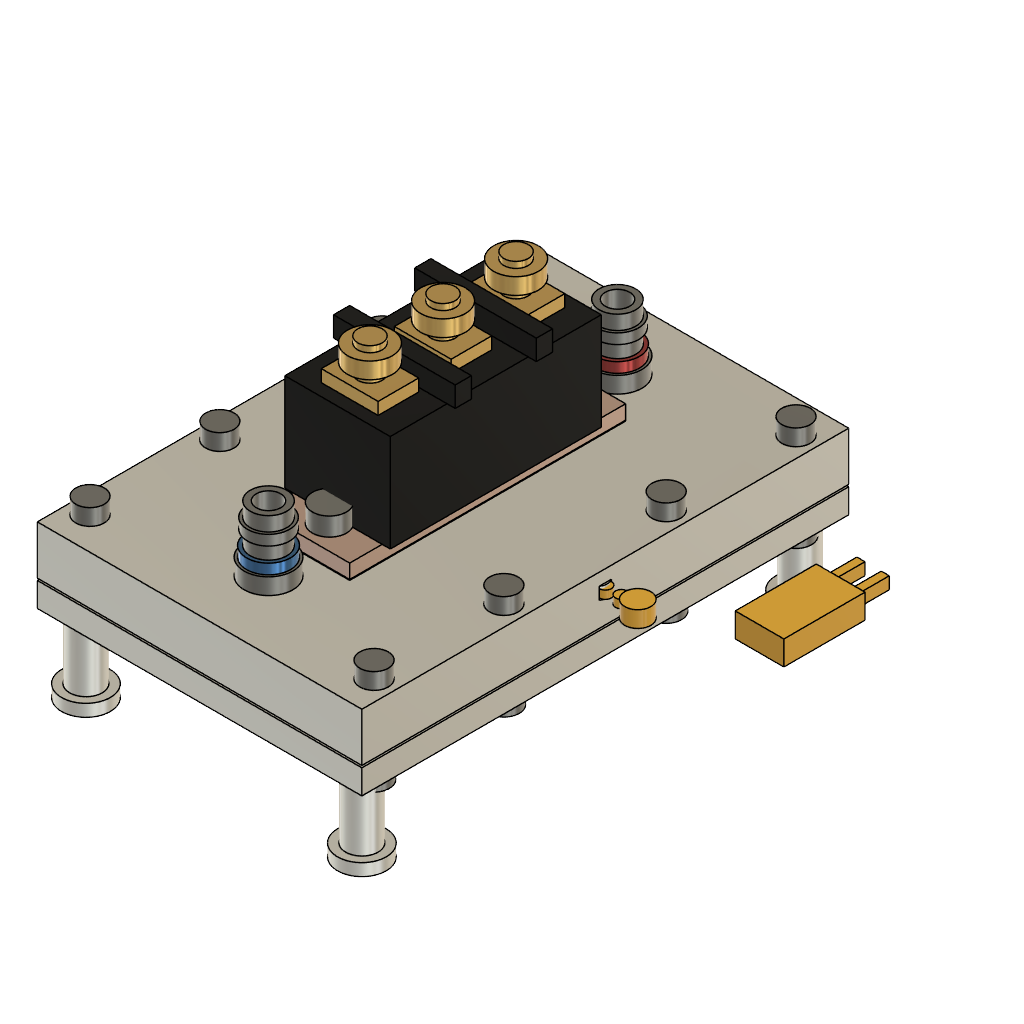
Before_Review_Backup (Autodesk Fusion 360 design; units mm, degrees)
part number: 2026-11-02-01-28-30-721
part number: 2026-11-02-02-59-40-221
part number: 2026-11-02-02-59-43-084
part number: 2026-11-02-02-59-43-519
part number: 2026-11-02-02-59-44-128
part number: 2026-11-02-02-59-44-602
part number: 2026-11-02-02-59-44-987
part number: 2026-11-02-02-59-46-241
part number: 2026-11-02-02-59-47-034
part number: 2026-11-02-02-59-47-858
part number: 2026-11-02-02-59-48-789
part number: 2026-11-02-02-59-49-745
part number: 2026-11-02-02-59-54-096
part number: 2026-11-02-02-59-54-882
part number: 2026-11-02-02-59-56-951
part number: 2026-11-02-03-00-06-820
part number: 2026-11-02-03-00-18-161
part number: 2026-11-02-03-00-22-757
Autodesk Fusion 360 part; units mm, degrees
(part 1 of 2)
ref_plane "WorkPlane1" through (0, 0, 0) normal (0, 0, 1) x (1, 0, 0) in component "01 Cold plate | 6061-T6 Aluminium | 120 x 80 x 12 mm"
sketch "Cold plate stock sketch" plane through (0, 0, 0) normal (0, 0, 1) x (1, 0, 0) in component "01 Cold plate | 6061-T6 Aluminium | 120 x 80 x 12 mm"
  line L0 (0, 0) -> (80, 0)
  line L1 (80, 0) -> (80, 120)
  line L2 (80, 120) -> (0, 120)
  line L3 (0, 120) -> (0, 0)
extrude "Cold plate stock" add sketch "Cold plate stock sketch" along normal blind 12 makes body 1 in component "01 Cold plate | 6061-T6 Aluminium | 120 x 80 x 12 mm"
ref_plane "WorkPlane2" through (0, 0, 0) normal (0, 0, 1) x (1, 0, 0) in component "01 Cold plate | 6061-T6 Aluminium | 120 x 80 x 12 mm"
sketch "16 Mini-Channels | 2 x 5 x 70 mm sketch" plane through (0, 0, 0) normal (0, 0, 1) x (1, 0, 0) in component "01 Cold plate | 6061-T6 Aluminium | 120 x 80 x 12 mm"
  line L0 (12.75, 25) -> (14.75, 25)
  line L1 (14.75, 25) -> (14.75, 95)
  line L2 (14.75, 95) -> (12.75, 95)
  line L3 (12.75, 95) -> (12.75, 25)
  line L4 (16.25, 25) -> (18.25, 25)
  line L5 (18.25, 25) -> (18.25, 95)
  line L6 (18.25, 95) -> (16.25, 95)
  line L7 (16.25, 95) -> (16.25, 25)
  line L8 (19.75, 25) -> (21.75, 25)
  line L9 (21.75, 25) -> (21.75, 95)
  line L10 (21.75, 95) -> (19.75, 95)
  line L11 (19.75, 95) -> (19.75, 25)
  line L12 (23.25, 25) -> (25.25, 25)
  line L13 (25.25, 25) -> (25.25, 95)
  line L14 (25.25, 95) -> (23.25, 95)
  line L15 (23.25, 95) -> (23.25, 25)
  line L16 (26.75, 25) -> (28.75, 25)
  line L17 (28.75, 25) -> (28.75, 95)
  line L18 (28.75, 95) -> (26.75, 95)
  line L19 (26.75, 95) -> (26.75, 25)
  line L20 (30.25, 25) -> (32.25, 25)
  line L21 (32.25, 25) -> (32.25, 95)
  line L22 (32.25, 95) -> (30.25, 95)
  line L23 (30.25, 95) -> (30.25, 25)
  line L24 (33.75, 25) -> (35.75, 25)
  line L25 (35.75, 25) -> (35.75, 95)
  line L26 (35.75, 95) -> (33.75, 95)
  line L27 (33.75, 95) -> (33.75, 25)
  line L28 (37.25, 25) -> (39.25, 25)
  line L29 (39.25, 25) -> (39.25, 95)
  line L30 (39.25, 95) -> (37.25, 95)
  line L31 (37.25, 95) -> (37.25, 25)
  line L32 (40.75, 25) -> (42.75, 25)
  line L33 (42.75, 25) -> (42.75, 95)
  line L34 (42.75, 95) -> (40.75, 95)
  line L35 (40.75, 95) -> (40.75, 25)
  line L36 (44.25, 25) -> (46.25, 25)
  line L37 (46.25, 25) -> (46.25, 95)
  line L38 (46.25, 95) -> (44.25, 95)
  line L39 (44.25, 95) -> (44.25, 25)
  line L40 (47.75, 25) -> (49.75, 25)
  line L41 (49.75, 25) -> (49.75, 95)
  line L42 (49.75, 95) -> (47.75, 95)
  line L43 (47.75, 95) -> (47.75, 25)
  line L44 (51.25, 25) -> (53.25, 25)
  line L45 (53.25, 25) -> (53.25, 95)
  line L46 (53.25, 95) -> (51.25, 95)
  line L47 (51.25, 95) -> (51.25, 25)
  line L48 (54.75, 25) -> (56.75, 25)
  line L49 (56.75, 25) -> (56.75, 95)
  line L50 (56.75, 95) -> (54.75, 95)
  line L51 (54.75, 95) -> (54.75, 25)
  line L52 (58.25, 25) -> (60.25, 25)
  line L53 (60.25, 25) -> (60.25, 95)
  line L54 (60.25, 95) -> (58.25, 95)
  line L55 (58.25, 95) -> (58.25, 25)
  line L56 (61.75, 25) -> (63.75, 25)
  line L57 (63.75, 25) -> (63.75, 95)
  line L58 (63.75, 95) -> (61.75, 95)
  line L59 (61.75, 95) -> (61.75, 25)
  line L60 (65.25, 25) -> (67.25, 25)
  line L61 (67.25, 25) -> (67.25, 95)
  line L62 (67.25, 95) -> (65.25, 95)
  line L63 (65.25, 95) -> (65.25, 25)
extrude "16 Mini-Channels | 2 x 5 x 70 mm" cut sketch "16 Mini-Channels | 2 x 5 x 70 mm sketch" along normal blind 5 bodies 1 in component "01 Cold plate | 6061-T6 Aluminium | 120 x 80 x 12 mm"
ref_plane "WorkPlane3" through (0, 0, 0) normal (0, 0, 1) x (1, 0, 0) in component "01 Cold plate | 6061-T6 Aluminium | 120 x 80 x 12 mm"
sketch "Headers sketch" plane through (0, 0, 0) normal (0, 0, 1) x (1, 0, 0) in component "01 Cold plate | 6061-T6 Aluminium | 120 x 80 x 12 mm"
  line L0 (10, 10) -> (70, 10)
  line L1 (70, 10) -> (70, 25)
  line L2 (70, 25) -> (10, 25)
  line L3 (10, 25) -> (10, 10)
  line L4 (10, 95) -> (70, 95)
  line L5 (70, 95) -> (70, 110)
  line L6 (70, 110) -> (10, 110)
  line L7 (10, 110) -> (10, 95)
extrude "Headers" cut sketch "Headers sketch" along normal blind 5 bodies 1 in component "01 Cold plate | 6061-T6 Aluminium | 120 x 80 x 12 mm"
ref_plane "WorkPlane4" through (0, 0, 0) normal (0, 0, 1) x (1, 0, 0) in component "01 Cold plate | 6061-T6 Aluminium | 120 x 80 x 12 mm"
sketch "Boundary-layer breaks sketch" plane through (0, 0, 0) normal (0, 0, 1) x (1, 0, 0) in component "01 Cold plate | 6061-T6 Aluminium | 120 x 80 x 12 mm"
  line L0 (14.7, 42) -> (16.3, 42)
  line L1 (16.3, 42) -> (16.3, 44.5)
  line L2 (16.3, 44.5) -> (14.7, 44.5)
  line L3 (14.7, 44.5) -> (14.7, 42)
  line L4 (14.7, 68) -> (16.3, 68)
  line L5 (16.3, 68) -> (16.3, 70.5)
  line L6 (16.3, 70.5) -> (14.7, 70.5)
  line L7 (14.7, 70.5) -> (14.7, 68)
  line L8 (18.2, 52) -> (19.8, 52)
  line L9 (19.8, 52) -> (19.8, 54.5)
  line L10 (19.8, 54.5) -> (18.2, 54.5)
  line L11 (18.2, 54.5) -> (18.2, 52)
  line L12 (18.2, 78) -> (19.8, 78)
  line L13 (19.8, 78) -> (19.8, 80.5)
  line L14 (19.8, 80.5) -> (18.2, 80.5)
  line L15 (18.2, 80.5) -> (18.2, 78)
  line L16 (21.7, 42) -> (23.3, 42)
  line L17 (23.3, 42) -> (23.3, 44.5)
  line L18 (23.3, 44.5) -> (21.7, 44.5)
  line L19 (21.7, 44.5) -> (21.7, 42)
  line L20 (21.7, 68) -> (23.3, 68)
  line L21 (23.3, 68) -> (23.3, 70.5)
  line L22 (23.3, 70.5) -> (21.7, 70.5)
  line L23 (21.7, 70.5) -> (21.7, 68)
  line L24 (25.2, 52) -> (26.8, 52)
  line L25 (26.8, 52) -> (26.8, 54.5)
  line L26 (26.8, 54.5) -> (25.2, 54.5)
  line L27 (25.2, 54.5) -> (25.2, 52)
  line L28 (25.2, 78) -> (26.8, 78)
  line L29 (26.8, 78) -> (26.8, 80.5)
  line L30 (26.8, 80.5) -> (25.2, 80.5)
  line L31 (25.2, 80.5) -> (25.2, 78)
  line L32 (28.7, 42) -> (30.3, 42)
  line L33 (30.3, 42) -> (30.3, 44.5)
  line L34 (30.3, 44.5) -> (28.7, 44.5)
  line L35 (28.7, 44.5) -> (28.7, 42)
  line L36 (28.7, 68) -> (30.3, 68)
  line L37 (30.3, 68) -> (30.3, 70.5)
  line L38 (30.3, 70.5) -> (28.7, 70.5)
  line L39 (28.7, 70.5) -> (28.7, 68)
  line L40 (32.2, 52) -> (33.8, 52)
  line L41 (33.8, 52) -> (33.8, 54.5)
  line L42 (33.8, 54.5) -> (32.2, 54.5)
  line L43 (32.2, 54.5) -> (32.2, 52)
  line L44 (32.2, 78) -> (33.8, 78)
  line L45 (33.8, 78) -> (33.8, 80.5)
  line L46 (33.8, 80.5) -> (32.2, 80.5)
  line L47 (32.2, 80.5) -> (32.2, 78)
  line L48 (35.7, 42) -> (37.3, 42)
  line L49 (37.3, 42) -> (37.3, 44.5)
  line L50 (37.3, 44.5) -> (35.7, 44.5)
  line L51 (35.7, 44.5) -> (35.7, 42)
  line L52 (35.7, 68) -> (37.3, 68)
  line L53 (37.3, 68) -> (37.3, 70.5)
  line L54 (37.3, 70.5) -> (35.7, 70.5)
  line L55 (35.7, 70.5) -> (35.7, 68)
  line L56 (39.2, 52) -> (40.8, 52)
  line L57 (40.8, 52) -> (40.8, 54.5)
  line L58 (40.8, 54.5) -> (39.2, 54.5)
  line L59 (39.2, 54.5) -> (39.2, 52)
  line L60 (39.2, 78) -> (40.8, 78)
  line L61 (40.8, 78) -> (40.8, 80.5)
  line L62 (40.8, 80.5) -> (39.2, 80.5)
  line L63 (39.2, 80.5) -> (39.2, 78)
  line L64 (42.7, 42) -> (44.3, 42)
  line L65 (44.3, 42) -> (44.3, 44.5)
  line L66 (44.3, 44.5) -> (42.7, 44.5)
  line L67 (42.7, 44.5) -> (42.7, 42)
  line L68 (42.7, 68) -> (44.3, 68)
  line L69 (44.3, 68) -> (44.3, 70.5)
  line L70 (44.3, 70.5) -> (42.7, 70.5)
  line L71 (42.7, 70.5) -> (42.7, 68)
  line L72 (46.2, 52) -> (47.8, 52)
  line L73 (47.8, 52) -> (47.8, 54.5)
  line L74 (47.8, 54.5) -> (46.2, 54.5)
  line L75 (46.2, 54.5) -> (46.2, 52)
  line L76 (46.2, 78) -> (47.8, 78)
  line L77 (47.8, 78) -> (47.8, 80.5)
  line L78 (47.8, 80.5) -> (46.2, 80.5)
  line L79 (46.2, 80.5) -> (46.2, 78)
  line L80 (49.7, 42) -> (51.3, 42)
  line L81 (51.3, 42) -> (51.3, 44.5)
  line L82 (51.3, 44.5) -> (49.7, 44.5)
  line L83 (49.7, 44.5) -> (49.7, 42)
  line L84 (49.7, 68) -> (51.3, 68)
  line L85 (51.3, 68) -> (51.3, 70.5)
  line L86 (51.3, 70.5) -> (49.7, 70.5)
  line L87 (49.7, 70.5) -> (49.7, 68)
  line L88 (53.2, 52) -> (54.8, 52)
  line L89 (54.8, 52) -> (54.8, 54.5)
  line L90 (54.8, 54.5) -> (53.2, 54.5)
  line L91 (53.2, 54.5) -> (53.2, 52)
  line L92 (53.2, 78) -> (54.8, 78)
  line L93 (54.8, 78) -> (54.8, 80.5)
  line L94 (54.8, 80.5) -> (53.2, 80.5)
  line L95 (53.2, 80.5) -> (53.2, 78)
  line L96 (56.7, 42) -> (58.3, 42)
  line L97 (58.3, 42) -> (58.3, 44.5)
  line L98 (58.3, 44.5) -> (56.7, 44.5)
  line L99 (56.7, 44.5) -> (56.7, 42)
  line L100 (56.7, 68) -> (58.3, 68)
  line L101 (58.3, 68) -> (58.3, 70.5)
  line L102 (58.3, 70.5) -> (56.7, 70.5)
  line L103 (56.7, 70.5) -> (56.7, 68)
  line L104 (60.2, 52) -> (61.8, 52)
  line L105 (61.8, 52) -> (61.8, 54.5)
  line L106 (61.8, 54.5) -> (60.2, 54.5)
  line L107 (60.2, 54.5) -> (60.2, 52)
  line L108 (60.2, 78) -> (61.8, 78)
  line L109 (61.8, 78) -> (61.8, 80.5)
  line L110 (61.8, 80.5) -> (60.2, 80.5)
  line L111 (60.2, 80.5) -> (60.2, 78)
  line L112 (63.7, 42) -> (65.3, 42)
  line L113 (65.3, 42) -> (65.3, 44.5)
  line L114 (65.3, 44.5) -> (63.7, 44.5)
  line L115 (63.7, 44.5) -> (63.7, 42)
  line L116 (63.7, 68) -> (65.3, 68)
  line L117 (65.3, 68) -> (65.3, 70.5)
  line L118 (65.3, 70.5) -> (63.7, 70.5)
  line L119 (63.7, 70.5) -> (63.7, 68)
extrude "Boundary-layer breaks" cut sketch "Boundary-layer breaks sketch" along normal blind 5 bodies 1 in component "01 Cold plate | 6061-T6 Aluminium | 120 x 80 x 12 mm"
ref_plane "WorkPlane5" through (0, 0, 0) normal (0, 0, 1) x (1, 0, 0) in component "01 Cold plate | 6061-T6 Aluminium | 120 x 80 x 12 mm"
sketch "Gasket groove 1 sketch" plane through (0, 0, 0) normal (0, 0, 1) x (1, 0, 0) in component "01 Cold plate | 6061-T6 Aluminium | 120 x 80 x 12 mm"
  line L0 (7, 7) -> (73, 7)
  line L1 (73, 7) -> (73, 9)
  line L2 (73, 9) -> (7, 9)
  line L3 (7, 9) -> (7, 7)
extrude "Gasket groove 1" cut sketch "Gasket groove 1 sketch" along normal blind 0.5 bodies 1 in component "01 Cold plate | 6061-T6 Aluminium | 120 x 80 x 12 mm"
ref_plane "WorkPlane6" through (0, 0, 0) normal (0, 0, 1) x (1, 0, 0) in component "01 Cold plate | 6061-T6 Aluminium | 120 x 80 x 12 mm"
sketch "Gasket groove 2 sketch" plane through (0, 0, 0) normal (0, 0, 1) x (1, 0, 0) in component "01 Cold plate | 6061-T6 Aluminium | 120 x 80 x 12 mm"
  line L0 (7, 111) -> (73, 111)
  line L1 (73, 111) -> (73, 113)
  line L2 (73, 113) -> (7, 113)
  line L3 (7, 113) -> (7, 111)
extrude "Gasket groove 2" cut sketch "Gasket groove 2 sketch" along normal blind 0.5 bodies 1 in component "01 Cold plate | 6061-T6 Aluminium | 120 x 80 x 12 mm"
ref_plane "WorkPlane7" through (0, 0, 0) normal (0, 0, 1) x (1, 0, 0) in component "01 Cold plate | 6061-T6 Aluminium | 120 x 80 x 12 mm"
sketch "Gasket groove 3 sketch" plane through (0, 0, 0) normal (0, 0, 1) x (1, 0, 0) in component "01 Cold plate | 6061-T6 Aluminium | 120 x 80 x 12 mm"
  line L0 (7, 9) -> (9, 9)
  line L1 (9, 9) -> (9, 111)
  line L2 (9, 111) -> (7, 111)
  line L3 (7, 111) -> (7, 9)
extrude "Gasket groove 3" cut sketch "Gasket groove 3 sketch" along normal blind 0.5 bodies 1 in component "01 Cold plate | 6061-T6 Aluminium | 120 x 80 x 12 mm"
ref_plane "WorkPlane8" through (0, 0, 0) normal (0, 0, 1) x (1, 0, 0) in component "01 Cold plate | 6061-T6 Aluminium | 120 x 80 x 12 mm"
sketch "Gasket groove 4 sketch" plane through (0, 0, 0) normal (0, 0, 1) x (1, 0, 0) in component "01 Cold plate | 6061-T6 Aluminium | 120 x 80 x 12 mm"
  line L0 (71, 9) -> (73, 9)
  line L1 (73, 9) -> (73, 111)
  line L2 (73, 111) -> (71, 111)
  line L3 (71, 111) -> (71, 9)
extrude "Gasket groove 4" cut sketch "Gasket groove 4 sketch" along normal blind 0.5 bodies 1 in component "01 Cold plate | 6061-T6 Aluminium | 120 x 80 x 12 mm"
ref_plane "WorkPlane9" through (0, 0, 12) normal (0, 0, 1) x (1, 0, 0) in component "01 Cold plate | 6061-T6 Aluminium | 120 x 80 x 12 mm"
sketch "Fluid port through-bores sketch" plane through (0, 0, 12) normal (0, 0, 1) x (1, 0, 0) in component "01 Cold plate | 6061-T6 Aluminium | 120 x 80 x 12 mm"
  circle A0 centre (40, 17) radius 3
  circle A1 centre (40, 103) radius 3
extrude "Fluid port through-bores" cut sketch "Fluid port through-bores sketch" against normal blind 7 bodies 1 in component "01 Cold plate | 6061-T6 Aluminium | 120 x 80 x 12 mm"
ref_plane "WorkPlane10" through (0, 0, 12) normal (0, 0, 1) x (1, 0, 0) in component "01 Cold plate | 6061-T6 Aluminium | 120 x 80 x 12 mm"
sketch "Cover bolt holes sketch" plane through (0, 0, 12) normal (0, 0, 1) x (1, 0, 0) in component "01 Cold plate | 6061-T6 Aluminium | 120 x 80 x 12 mm"
  circle A0 centre (5, 8) radius 2.2
  circle A1 centre (75, 8) radius 2.2
  circle A2 centre (5, 40) radius 2.2
  circle A3 centre (75, 40) radius 2.2
  circle A4 centre (5, 80) radius 2.2
  circle A5 centre (75, 80) radius 2.2
  circle A6 centre (5, 112) radius 2.2
  circle A7 centre (75, 112) radius 2.2
extrude "Cover bolt holes" cut sketch "Cover bolt holes sketch" against normal blind 12 bodies 1 in component "01 Cold plate | 6061-T6 Aluminium | 120 x 80 x 12 mm"
ref_plane "WorkPlane11" through (0, 0, 12) normal (0, 0, 1) x (1, 0, 0) in component "01 Cold plate | 6061-T6 Aluminium | 120 x 80 x 12 mm"
sketch "SCR M5 tapped holes sketch" plane through (0, 0, 12) normal (0, 0, 1) x (1, 0, 0) in component "01 Cold plate | 6061-T6 Aluminium | 120 x 80 x 12 mm"
  circle A0 centre (40, 32) radius 2.1
  circle A1 centre (40, 88) radius 2.1
extrude "SCR M5 tapped holes" cut sketch "SCR M5 tapped holes sketch" against normal blind 8 bodies 1 in component "01 Cold plate | 6061-T6 Aluminium | 120 x 80 x 12 mm"
ref_plane "WorkPlane12" through (0, 0, 6) normal (0, 0, 1) x (1, 0, 0) in component "01 Cold plate | 6061-T6 Aluminium | 120 x 80 x 12 mm"
sketch "Thermowell entry boss sketch" plane through (0, 0, 6) normal (0, 0, 1) x (1, 0, 0) in component "01 Cold plate | 6061-T6 Aluminium | 120 x 80 x 12 mm"
  circle A0 centre (78, 60) radius 2.5
extrude "Thermowell entry boss" add sketch "Thermowell entry boss sketch" along normal blind 3 bodies 1 in component "01 Cold plate | 6061-T6 Aluminium | 120 x 80 x 12 mm"
ref_plane "WorkPlane1" through (0, 0, 0) normal (0, 0, 1) x (1, 0, 0) in component "02 Perimeter sealing gasket | 0.5 mm silicone"
sketch "Gasket blank sketch" plane through (0, 0, 0) normal (0, 0, 1) x (1, 0, 0) in component "02 Perimeter sealing gasket | 0.5 mm silicone"
  line L0 (7, 7) -> (73, 7)
  line L1 (73, 7) -> (73, 113)
  line L2 (73, 113) -> (7, 113)
  line L3 (7, 113) -> (7, 7)
extrude "Gasket blank" add sketch "Gasket blank sketch" against normal blind 0.5 separate body makes body 2 in component "02 Perimeter sealing gasket | 0.5 mm silicone"
ref_plane "WorkPlane2" through (0, 0, 0) normal (0, 0, 1) x (1, 0, 0) in component "02 Perimeter sealing gasket | 0.5 mm silicone"
sketch "Gasket fluid aperture sketch" plane through (0, 0, 0) normal (0, 0, 1) x (1, 0, 0) in component "02 Perimeter sealing gasket | 0.5 mm silicone"
  line L0 (9, 9) -> (71, 9)
  line L1 (71, 9) -> (71, 111)
  line L2 (71, 111) -> (9, 111)
  line L3 (9, 111) -> (9, 9)
extrude "Gasket fluid aperture" cut sketch "Gasket fluid aperture sketch" against normal blind 0.5 bodies 2 in component "02 Perimeter sealing gasket | 0.5 mm silicone"
ref_plane "WorkPlane1" through (0, 0, -0.5) normal (0, 0, 1) x (1, 0, 0) in component "03 Bottom manifold cover | 6061-T6 Aluminium"
sketch "Bottom cover slab sketch" plane through (0, 0, -0.5) normal (0, 0, 1) x (1, 0, 0) in component "03 Bottom manifold cover | 6061-T6 Aluminium"
  line L0 (0, 0) -> (80, 0)
  line L1 (80, 0) -> (80, 120)
  line L2 (80, 120) -> (0, 120)
  line L3 (0, 120) -> (0, 0)
extrude "Bottom cover slab" add sketch "Bottom cover slab sketch" against normal blind 6 separate body makes body 3 in component "03 Bottom manifold cover | 6061-T6 Aluminium"
ref_plane "WorkPlane2" through (0, 0, -0.5) normal (0, 0, 1) x (1, 0, 0) in component "03 Bottom manifold cover | 6061-T6 Aluminium"
sketch "Cover bolt holes sketch (2)" plane through (0, 0, -0.5) normal (0, 0, 1) x (1, 0, 0) in component "03 Bottom manifold cover | 6061-T6 Aluminium"
  circle A0 centre (5, 8) radius 2.2
  circle A1 centre (75, 8) radius 2.2
  circle A2 centre (5, 40) radius 2.2
  circle A3 centre (75, 40) radius 2.2
  circle A4 centre (5, 80) radius 2.2
  circle A5 centre (75, 80) radius 2.2
  circle A6 centre (5, 112) radius 2.2
  circle A7 centre (75, 112) radius 2.2
extrude "Cover bolt holes'" cut sketch "Cover bolt holes sketch (2)" against normal blind 6 bodies 3 in component "03 Bottom manifold cover | 6061-T6 Aluminium"
ref_plane "WorkPlane1" through (0, 0, 12) normal (0, 0, 1) x (1, 0, 0) in component "04 Inlet hose barb fitting | 6 mm bore"
sketch "Hex collar sketch" plane through (0, 0, 12) normal (0, 0, 1) x (1, 0, 0) in component "04 Inlet hose barb fitting | 6 mm bore"
  circle A0 centre (40, 17) radius 6
extrude "Hex collar" add sketch "Hex collar sketch" along normal blind 4 separate body makes body 4 in component "04 Inlet hose barb fitting | 6 mm bore"
ref_plane "WorkPlane2" through (0, 0, 16) normal (0, 0, 1) x (1, 0, 0) in component "04 Inlet hose barb fitting | 6 mm bore"
sketch "Barb stem sketch" plane through (0, 0, 16) normal (0, 0, 1) x (1, 0, 0) in component "04 Inlet hose barb fitting | 6 mm bore"
  circle A0 centre (40, 17) radius 4.5
extrude "Barb stem" add sketch "Barb stem sketch" along normal blind 12 bodies 4 in component "04 Inlet hose barb fitting | 6 mm bore"
ref_plane "WorkPlane3" through (0, 0, 22) normal (0, 0, 1) x (1, 0, 0) in component "04 Inlet hose barb fitting | 6 mm bore"
sketch "Retention barb bead sketch" plane through (0, 0, 22) normal (0, 0, 1) x (1, 0, 0) in component "04 Inlet hose barb fitting | 6 mm bore"
  circle A0 centre (40, 17) radius 5.2
extrude "Retention barb bead" add sketch "Retention barb bead sketch" along normal blind 2.5 bodies 4 in component "04 Inlet hose barb fitting | 6 mm bore"
ref_plane "WorkPlane4" through (0, 0, 28) normal (0, 0, 1) x (1, 0, 0) in component "04 Inlet hose barb fitting | 6 mm bore"
sketch "Continuous fluid bore sketch" plane through (0, 0, 28) normal (0, 0, 1) x (1, 0, 0) in component "04 Inlet hose barb fitting | 6 mm bore"
  circle A0 centre (40, 17) radius 3
extrude "Continuous fluid bore" cut sketch "Continuous fluid bore sketch" against normal blind 16 bodies 4 in component "04 Inlet hose barb fitting | 6 mm bore"
ref_plane "WorkPlane1" through (0, 0, 16) normal (0, 0, 1) x (1, 0, 0) in component "05 Inlet anodized identification ring"
sketch "Identifier ring sketch" plane through (0, 0, 16) normal (0, 0, 1) x (1, 0, 0) in component "05 Inlet anodized identification ring"
  circle A0 centre (40, 17) radius 5.4
extrude "Identifier ring" add sketch "Identifier ring sketch" along normal blind 2.5 separate body makes body 5 in component "05 Inlet anodized identification ring"
ref_plane "WorkPlane2" through (0, 0, 16) normal (0, 0, 1) x (1, 0, 0) in component "05 Inlet anodized identification ring"
sketch "Ring bore sketch" plane through (0, 0, 16) normal (0, 0, 1) x (1, 0, 0) in component "05 Inlet anodized identification ring"
  circle A0 centre (40, 17) radius 4.5
extrude "Ring bore" cut sketch "Ring bore sketch" along normal blind 2.5 bodies 4 makes body 6 at (45.9702, 16.4026, 13.3333) in component "04 Inlet hose barb fitting | 6 mm bore"
extrude "Extrude2" cut sketch "Ring bore sketch" along normal blind 2.5 bodies 5 in component "05 Inlet anodized identification ring"
ref_plane "WorkPlane1" through (0, 0, 12) normal (0, 0, 1) x (1, 0, 0) in component "04 Outlet hose barb fitting | 6 mm bore"
sketch "Hex collar sketch (2)" plane through (0, 0, 12) normal (0, 0, 1) x (1, 0, 0) in component "04 Outlet hose barb fitting | 6 mm bore"
  circle A0 centre (40, 103) radius 6
extrude "Hex collar'" add sketch "Hex collar sketch (2)" along normal blind 4 separate body makes body 7 in component "04 Outlet hose barb fitting | 6 mm bore"
ref_plane "WorkPlane2" through (0, 0, 16) normal (0, 0, 1) x (1, 0, 0) in component "04 Outlet hose barb fitting | 6 mm bore"
sketch "Barb stem sketch (2)" plane through (0, 0, 16) normal (0, 0, 1) x (1, 0, 0) in component "04 Outlet hose barb fitting | 6 mm bore"
  circle A0 centre (40, 103) radius 4.5
extrude "Barb stem'" add sketch "Barb stem sketch (2)" along normal blind 12 bodies 7 in component "04 Outlet hose barb fitting | 6 mm bore"
ref_plane "WorkPlane3" through (0, 0, 22) normal (0, 0, 1) x (1, 0, 0) in component "04 Outlet hose barb fitting | 6 mm bore"
sketch "Retention barb bead sketch (2)" plane through (0, 0, 22) normal (0, 0, 1) x (1, 0, 0) in component "04 Outlet hose barb fitting | 6 mm bore"
  circle A0 centre (40, 103) radius 5.2
extrude "Retention barb bead'" add sketch "Retention barb bead sketch (2)" along normal blind 2.5 bodies 7 in component "04 Outlet hose barb fitting | 6 mm bore"
ref_plane "WorkPlane4" through (0, 0, 28) normal (0, 0, 1) x (1, 0, 0) in component "04 Outlet hose barb fitting | 6 mm bore"
sketch "Continuous fluid bore sketch (2)" plane through (0, 0, 28) normal (0, 0, 1) x (1, 0, 0) in component "04 Outlet hose barb fitting | 6 mm bore"
  circle A0 centre (40, 103) radius 3
extrude "Continuous fluid bore'" cut sketch "Continuous fluid bore sketch (2)" against normal blind 16 bodies 7 in component "04 Outlet hose barb fitting | 6 mm bore"
ref_plane "WorkPlane1" through (0, 0, 16) normal (0, 0, 1) x (1, 0, 0) in component "05 Outlet anodized identification ring"
sketch "Identifier ring sketch (2)" plane through (0, 0, 16) normal (0, 0, 1) x (1, 0, 0) in component "05 Outlet anodized identification ring"
  circle A0 centre (40, 103) radius 5.4
extrude "Identifier ring'" add sketch "Identifier ring sketch (2)" along normal blind 2.5 separate body makes body 8 in component "05 Outlet anodized identification ring"
ref_plane "WorkPlane2" through (0, 0, 16) normal (0, 0, 1) x (1, 0, 0) in component "05 Outlet anodized identification ring"
sketch "Ring bore sketch (2)" plane through (0, 0, 16) normal (0, 0, 1) x (1, 0, 0) in component "05 Outlet anodized identification ring"
  circle A0 centre (40, 103) radius 4.5
extrude "Ring bore'" cut sketch "Ring bore sketch (2)" along normal blind 2.5 bodies 7 makes body 9 at (45.9702, 102.4026, 13.3333) in component "04 Outlet hose barb fitting | 6 mm bore"
extrude "Extrude2'" cut sketch "Ring bore sketch (2)" along normal blind 2.5 bodies 8 in component "05 Outlet anodized identification ring"
ref_plane "WorkPlane1" through (0, 0, 12) normal (0, 0, 1) x (1, 0, 0) in component "06 Thermal interface pad (TIM) | 0.2 mm"
sketch "TIM envelope sketch" plane through (0, 0, 12) normal (0, 0, 1) x (1, 0, 0) in component "06 Thermal interface pad (TIM) | 0.2 mm"
  line L0 (29, 26) -> (51, 26)
  line L1 (51, 26) -> (51, 94)
  line L2 (51, 94) -> (29, 94)
  line L3 (29, 94) -> (29, 26)
extrude "TIM envelope" add sketch "TIM envelope sketch" along normal blind 0.2 separate body makes body 10 in component "06 Thermal interface pad (TIM) | 0.2 mm"
ref_plane "WorkPlane2" through (0, 0, 12) normal (0, 0, 1) x (1, 0, 0) in component "06 Thermal interface pad (TIM) | 0.2 mm"
sketch "TIM bolt clearance sketch" plane through (0, 0, 12) normal (0, 0, 1) x (1, 0, 0) in component "06 Thermal interface pad (TIM) | 0.2 mm"
  circle A0 centre (40, 32) radius 2.5
  circle A1 centre (40, 88) radius 2.5
extrude "TIM bolt clearance" cut sketch "TIM bolt clearance sketch" along normal blind 0.2 bodies 10 in component "06 Thermal interface pad (TIM) | 0.2 mm"
ref_plane "WorkPlane1" through (0, 0, 12.2) normal (0, 0, 1) x (1, 0, 0) in component "07 SCR copper baseplate | 92 x 22 x 3.5 mm"
sketch "Copper baseplate sketch" plane through (0, 0, 12.2) normal (0, 0, 1) x (1, 0, 0) in component "07 SCR copper baseplate | 92 x 22 x 3.5 mm"
  line L0 (29, 26) -> (51, 26)
  line L1 (51, 26) -> (51, 94)
  line L2 (51, 94) -> (29, 94)
  line L3 (29, 94) -> (29, 26)
extrude "Copper baseplate" add sketch "Copper baseplate sketch" along normal blind 3.5 separate body makes body 11 in component "07 SCR copper baseplate | 92 x 22 x 3.5 mm"
ref_plane "WorkPlane2" through (0, 0, 12.2) normal (0, 0, 1) x (1, 0, 0) in component "07 SCR copper baseplate | 92 x 22 x 3.5 mm"
sketch "U-bolt mounting slots sketch" plane through (0, 0, 12.2) normal (0, 0, 1) x (1, 0, 0) in component "07 SCR copper baseplate | 92 x 22 x 3.5 mm"
  circle A0 centre (40, 32) radius 2.6
  circle A1 centre (40, 88) radius 2.6
extrude "U-bolt mounting slots" cut sketch "U-bolt mounting slots sketch" along normal blind 3.5 bodies 11 in component "07 SCR copper baseplate | 92 x 22 x 3.5 mm"
ref_plane "WorkPlane1" through (0, 0, 15.7) normal (0, 0, 1) x (1, 0, 0) in component "08 Thyristor housing | TY160D40 Molded PBT"
sketch "SCR plastic body sketch" plane through (0, 0, 15.7) normal (0, 0, 1) x (1, 0, 0) in component "08 Thyristor housing | TY160D40 Molded PBT"
  line L0 (27, 34) -> (53, 34)
  line L1 (53, 34) -> (53, 86)
  line L2 (53, 86) -> (27, 86)
  line L3 (27, 86) -> (27, 34)
extrude "SCR plastic body" add sketch "SCR plastic body sketch" along normal blind 24 separate body makes body 12 in component "08 Thyristor housing | TY160D40 Molded PBT"
ref_plane "WorkPlane2" through (0, 0, 39.7) normal (0, 0, 1) x (1, 0, 0) in component "08 Thyristor housing | TY160D40 Molded PBT"
sketch "Phase isolation barriers sketch" plane through (0, 0, 39.7) normal (0, 0, 1) x (1, 0, 0) in component "08 Thyristor housing | TY160D40 Molded PBT"
  line L0 (25, 48) -> (55, 48)
  line L1 (55, 48) -> (55, 52)
  line L2 (55, 52) -> (25, 52)
  line L3 (25, 52) -> (25, 48)
  line L4 (25, 68) -> (55, 68)
  line L5 (55, 68) -> (55, 72)
  line L6 (55, 72) -> (25, 72)
  line L7 (25, 72) -> (25, 68)
extrude "Phase isolation barriers" add sketch "Phase isolation barriers sketch" along normal blind 5 bodies 12 in component "08 Thyristor housing | TY160D40 Molded PBT"
ref_plane "WorkPlane1" through (0, 0, 39.7) normal (0, 0, 1) x (1, 0, 0) in component "09 Power terminals | Copper pads & M6 Brass studs"
sketch "Pad_42.0 sketch" plane through (0, 0, 39.7) normal (0, 0, 1) x (1, 0, 0) in component "09 Power terminals | Copper pads & M6 Brass studs"
  line L0 (33, 37) -> (47, 37)
  line L1 (47, 37) -> (47, 47)
  line L2 (47, 47) -> (33, 47)
  line L3 (33, 47) -> (33, 37)
extrude "Pad_42.0" add sketch "Pad_42.0 sketch" along normal blind 3 separate body makes body 13 in component "09 Power terminals | Copper pads & M6 Brass studs"
ref_plane "WorkPlane2" through (0, 0, 42.7) normal (0, 0, 1) x (1, 0, 0) in component "09 Power terminals | Copper pads & M6 Brass studs"
sketch "Stud_42.0 sketch" plane through (0, 0, 42.7) normal (0, 0, 1) x (1, 0, 0) in component "09 Power terminals | Copper pads & M6 Brass studs"
  circle A0 centre (40, 42) radius 3
extrude "Stud_42.0" add sketch "Stud_42.0 sketch" along normal blind 8 bodies 13 in component "09 Power terminals | Copper pads & M6 Brass studs"
ref_plane "WorkPlane3" through (0, 0, 45.2) normal (0, 0, 1) x (1, 0, 0) in component "09 Power terminals | Copper pads & M6 Brass studs"
sketch "Nut_42.0 sketch" plane through (0, 0, 45.2) normal (0, 0, 1) x (1, 0, 0) in component "09 Power terminals | Copper pads & M6 Brass studs"
  circle A0 centre (40, 42) radius 5.5
extrude "Nut_42.0" add sketch "Nut_42.0 sketch" along normal blind 4 bodies 13 in component "09 Power terminals | Copper pads & M6 Brass studs"
ref_plane "WorkPlane4" through (0, 0, 39.7) normal (0, 0, 1) x (1, 0, 0) in component "09 Power terminals | Copper pads & M6 Brass studs"
sketch "Pad_60.0 sketch" plane through (0, 0, 39.7) normal (0, 0, 1) x (1, 0, 0) in component "09 Power terminals | Copper pads & M6 Brass studs"
  line L0 (33, 55) -> (47, 55)
  line L1 (47, 55) -> (47, 65)
  line L2 (47, 65) -> (33, 65)
  line L3 (33, 65) -> (33, 55)
extrude "Pad_60.0" add sketch "Pad_60.0 sketch" along normal blind 3 separate body makes body 14 in component "09 Power terminals | Copper pads & M6 Brass studs"
ref_plane "WorkPlane5" through (0, 0, 42.7) normal (0, 0, 1) x (1, 0, 0) in component "09 Power terminals | Copper pads & M6 Brass studs"
sketch "Stud_60.0 sketch" plane through (0, 0, 42.7) normal (0, 0, 1) x (1, 0, 0) in component "09 Power terminals | Copper pads & M6 Brass studs"
  circle A0 centre (40, 60) radius 3
extrude "Stud_60.0" add sketch "Stud_60.0 sketch" along normal blind 8 bodies 14 in component "09 Power terminals | Copper pads & M6 Brass studs"
ref_plane "WorkPlane6" through (0, 0, 45.2) normal (0, 0, 1) x (1, 0, 0) in component "09 Power terminals | Copper pads & M6 Brass studs"
sketch "Nut_60.0 sketch" plane through (0, 0, 45.2) normal (0, 0, 1) x (1, 0, 0) in component "09 Power terminals | Copper pads & M6 Brass studs"
  circle A0 centre (40, 60) radius 5.5
extrude "Nut_60.0" add sketch "Nut_60.0 sketch" along normal blind 4 bodies 14 in component "09 Power terminals | Copper pads & M6 Brass studs"
ref_plane "WorkPlane7" through (0, 0, 39.7) normal (0, 0, 1) x (1, 0, 0) in component "09 Power terminals | Copper pads & M6 Brass studs"
sketch "Pad_78.0 sketch" plane through (0, 0, 39.7) normal (0, 0, 1) x (1, 0, 0) in component "09 Power terminals | Copper pads & M6 Brass studs"
  line L0 (33, 73) -> (47, 73)
  line L1 (47, 73) -> (47, 83)
  line L2 (47, 83) -> (33, 83)
  line L3 (33, 83) -> (33, 73)
extrude "Pad_78.0" add sketch "Pad_78.0 sketch" along normal blind 3 separate body makes body 15 in component "09 Power terminals | Copper pads & M6 Brass studs"
ref_plane "WorkPlane8" through (0, 0, 42.7) normal (0, 0, 1) x (1, 0, 0) in component "09 Power terminals | Copper pads & M6 Brass studs"
sketch "Stud_78.0 sketch" plane through (0, 0, 42.7) normal (0, 0, 1) x (1, 0, 0) in component "09 Power terminals | Copper pads & M6 Brass studs"
  circle A0 centre (40, 78) radius 3
extrude "Stud_78.0" add sketch "Stud_78.0 sketch" along normal blind 8 bodies 15 in component "09 Power terminals | Copper pads & M6 Brass studs"
ref_plane "WorkPlane9" through (0, 0, 45.2) normal (0, 0, 1) x (1, 0, 0) in component "09 Power terminals | Copper pads & M6 Brass studs"
sketch "Nut_78.0 sketch" plane through (0, 0, 45.2) normal (0, 0, 1) x (1, 0, 0) in component "09 Power terminals | Copper pads & M6 Brass studs"
  circle A0 centre (40, 78) radius 5.5
extrude "Nut_78.0" add sketch "Nut_78.0 sketch" along normal blind 4 bodies 15 in component "09 Power terminals | Copper pads & M6 Brass studs"
ref_plane "WorkPlane1" through (0, 0, 26) normal (0, 0, 1) x (1, 0, 0) in component "10 Gate & auxiliary trigger terminals"
sketch "Gate pins sketch" plane through (0, 0, 26) normal (0, 0, 1) x (1, 0, 0) in component "10 Gate & auxiliary trigger terminals"
  line L0 (26, 56) -> (27.5, 56)
  line L1 (27.5, 56) -> (27.5, 58.5)
  line L2 (27.5, 58.5) -> (26, 58.5)
  line L3 (26, 58.5) -> (26, 56)
  line L4 (26, 61.5) -> (27.5, 61.5)
  line L5 (27.5, 61.5) -> (27.5, 64)
  line L6 (27.5, 64) -> (26, 64)
  line L7 (26, 64) -> (26, 61.5)
extrude "Gate pins" add sketch "Gate pins sketch" along normal blind 6 separate body makes body 16 at (26, 57.6667, 28) makes body 17 at (26, 63.1667, 28) in component "10 Gate & auxiliary trigger terminals"
ref_plane "WorkPlane1" through (0, 0, 15.7) normal (0, 0, 1) x (1, 0, 0) in component "11 SCR M5 socket head cap screws"
sketch "Head_32.0 sketch" plane through (0, 0, 15.7) normal (0, 0, 1) x (1, 0, 0) in component "11 SCR M5 socket head cap screws"
  circle A0 centre (40, 32) radius 4.2
extrude "Head_32.0" add sketch "Head_32.0 sketch" along normal blind 4.5 separate body makes body 18 in component "11 SCR M5 socket head cap screws"
ref_plane "WorkPlane2" through (0, 0, 15.7) normal (0, 0, 1) x (1, 0, 0) in component "11 SCR M5 socket head cap screws"
sketch "Shank_32.0 sketch" plane through (0, 0, 15.7) normal (0, 0, 1) x (1, 0, 0) in component "11 SCR M5 socket head cap screws"
  circle A0 centre (40, 32) radius 2.4
extrude "Shank_32.0" add sketch "Shank_32.0 sketch" against normal blind 9 bodies 18 in component "11 SCR M5 socket head cap screws"
ref_plane "WorkPlane3" through (0, 0, 15.7) normal (0, 0, 1) x (1, 0, 0) in component "11 SCR M5 socket head cap screws"
sketch "Head_88.0 sketch" plane through (0, 0, 15.7) normal (0, 0, 1) x (1, 0, 0) in component "11 SCR M5 socket head cap screws"
  circle A0 centre (40, 88) radius 4.2
extrude "Head_88.0" add sketch "Head_88.0 sketch" along normal blind 4.5 separate body makes body 19 in component "11 SCR M5 socket head cap screws"
ref_plane "WorkPlane4" through (0, 0, 15.7) normal (0, 0, 1) x (1, 0, 0) in component "11 SCR M5 socket head cap screws"
sketch "Shank_88.0 sketch" plane through (0, 0, 15.7) normal (0, 0, 1) x (1, 0, 0) in component "11 SCR M5 socket head cap screws"
  circle A0 centre (40, 88) radius 2.4
extrude "Shank_88.0" add sketch "Shank_88.0 sketch" against normal blind 9 bodies 19 in component "11 SCR M5 socket head cap screws"
ref_plane "WorkPlane1" through (0, 0, 12) normal (0, 0, 1) x (1, 0, 0) in component "12 Cover perimeter bolts | 8x M4 socket cap screws"
sketch "BHead_5_8 sketch" plane through (0, 0, 12) normal (0, 0, 1) x (1, 0, 0) in component "12 Cover perimeter bolts | 8x M4 socket cap screws"
  circle A0 centre (5, 8) radius 3.5
extrude "BHead_5_8" add sketch "BHead_5_8 sketch" along normal blind 4 separate body makes body 20 in component "12 Cover perimeter bolts | 8x M4 socket cap screws"
ref_plane "WorkPlane2" through (0, 0, 12) normal (0, 0, 1) x (1, 0, 0) in component "12 Cover perimeter bolts | 8x M4 socket cap screws"
sketch "BShank_5_8 sketch" plane through (0, 0, 12) normal (0, 0, 1) x (1, 0, 0) in component "12 Cover perimeter bolts | 8x M4 socket cap screws"
  circle A0 centre (5, 8) radius 1.9
extrude "BShank_5_8" add sketch "BShank_5_8 sketch" against normal blind 18.5 bodies 20 in component "12 Cover perimeter bolts | 8x M4 socket cap screws"
ref_plane "WorkPlane3" through (0, 0, 12) normal (0, 0, 1) x (1, 0, 0) in component "12 Cover perimeter bolts | 8x M4 socket cap screws"
sketch "BHead_75_8 sketch" plane through (0, 0, 12) normal (0, 0, 1) x (1, 0, 0) in component "12 Cover perimeter bolts | 8x M4 socket cap screws"
  circle A0 centre (75, 8) radius 3.5
extrude "BHead_75_8" add sketch "BHead_75_8 sketch" along normal blind 4 separate body makes body 21 in component "12 Cover perimeter bolts | 8x M4 socket cap screws"
ref_plane "WorkPlane4" through (0, 0, 12) normal (0, 0, 1) x (1, 0, 0) in component "12 Cover perimeter bolts | 8x M4 socket cap screws"
sketch "BShank_75_8 sketch" plane through (0, 0, 12) normal (0, 0, 1) x (1, 0, 0) in component "12 Cover perimeter bolts | 8x M4 socket cap screws"
  circle A0 centre (75, 8) radius 1.9
extrude "BShank_75_8" add sketch "BShank_75_8 sketch" against normal blind 18.5 bodies 21 in component "12 Cover perimeter bolts | 8x M4 socket cap screws"
ref_plane "WorkPlane5" through (0, 0, 12) normal (0, 0, 1) x (1, 0, 0) in component "12 Cover perimeter bolts | 8x M4 socket cap screws"
sketch "BHead_5_40 sketch" plane through (0, 0, 12) normal (0, 0, 1) x (1, 0, 0) in component "12 Cover perimeter bolts | 8x M4 socket cap screws"
  circle A0 centre (5, 40) radius 3.5
extrude "BHead_5_40" add sketch "BHead_5_40 sketch" along normal blind 4 separate body makes body 22 in component "12 Cover perimeter bolts | 8x M4 socket cap screws"
ref_plane "WorkPlane6" through (0, 0, 12) normal (0, 0, 1) x (1, 0, 0) in component "12 Cover perimeter bolts | 8x M4 socket cap screws"
sketch "BShank_5_40 sketch" plane through (0, 0, 12) normal (0, 0, 1) x (1, 0, 0) in component "12 Cover perimeter bolts | 8x M4 socket cap screws"
  circle A0 centre (5, 40) radius 1.9
extrude "BShank_5_40" add sketch "BShank_5_40 sketch" against normal blind 18.5 bodies 22 in component "12 Cover perimeter bolts | 8x M4 socket cap screws"
ref_plane "WorkPlane7" through (0, 0, 12) normal (0, 0, 1) x (1, 0, 0) in component "12 Cover perimeter bolts | 8x M4 socket cap screws"
sketch "BHead_75_40 sketch" plane through (0, 0, 12) normal (0, 0, 1) x (1, 0, 0) in component "12 Cover perimeter bolts | 8x M4 socket cap screws"
  circle A0 centre (75, 40) radius 3.5
extrude "BHead_75_40" add sketch "BHead_75_40 sketch" along normal blind 4 separate body makes body 23 in component "12 Cover perimeter bolts | 8x M4 socket cap screws"
ref_plane "WorkPlane8" through (0, 0, 12) normal (0, 0, 1) x (1, 0, 0) in component "12 Cover perimeter bolts | 8x M4 socket cap screws"
sketch "BShank_75_40 sketch" plane through (0, 0, 12) normal (0, 0, 1) x (1, 0, 0) in component "12 Cover perimeter bolts | 8x M4 socket cap screws"
  circle A0 centre (75, 40) radius 1.9
extrude "BShank_75_40" add sketch "BShank_75_40 sketch" against normal blind 18.5 bodies 23 in component "12 Cover perimeter bolts | 8x M4 socket cap screws"
ref_plane "WorkPlane9" through (0, 0, 12) normal (0, 0, 1) x (1, 0, 0) in component "12 Cover perimeter bolts | 8x M4 socket cap screws"
sketch "BHead_5_80 sketch" plane through (0, 0, 12) normal (0, 0, 1) x (1, 0, 0) in component "12 Cover perimeter bolts | 8x M4 socket cap screws"
  circle A0 centre (5, 80) radius 3.5
extrude "BHead_5_80" add sketch "BHead_5_80 sketch" along normal blind 4 separate body makes body 24 in component "12 Cover perimeter bolts | 8x M4 socket cap screws"
ref_plane "WorkPlane10" through (0, 0, 12) normal (0, 0, 1) x (1, 0, 0) in component "12 Cover perimeter bolts | 8x M4 socket cap screws"
sketch "BShank_5_80 sketch" plane through (0, 0, 12) normal (0, 0, 1) x (1, 0, 0) in component "12 Cover perimeter bolts | 8x M4 socket cap screws"
  circle A0 centre (5, 80) radius 1.9
extrude "BShank_5_80" add sketch "BShank_5_80 sketch" against normal blind 18.5 bodies 24 in component "12 Cover perimeter bolts | 8x M4 socket cap screws"
ref_plane "WorkPlane11" through (0, 0, 12) normal (0, 0, 1) x (1, 0, 0) in component "12 Cover perimeter bolts | 8x M4 socket cap screws"
sketch "BHead_75_80 sketch" plane through (0, 0, 12) normal (0, 0, 1) x (1, 0, 0) in component "12 Cover perimeter bolts | 8x M4 socket cap screws"
  circle A0 centre (75, 80) radius 3.5
extrude "BHead_75_80" add sketch "BHead_75_80 sketch" along normal blind 4 separate body makes body 25 in component "12 Cover perimeter bolts | 8x M4 socket cap screws"
ref_plane "WorkPlane12" through (0, 0, 12) normal (0, 0, 1) x (1, 0, 0) in component "12 Cover perimeter bolts | 8x M4 socket cap screws"
sketch "BShank_75_80 sketch" plane through (0, 0, 12) normal (0, 0, 1) x (1, 0, 0) in component "12 Cover perimeter bolts | 8x M4 socket cap screws"
  circle A0 centre (75, 80) radius 1.9
extrude "BShank_75_80" add sketch "BShank_75_80 sketch" against normal blind 18.5 bodies 25 in component "12 Cover perimeter bolts | 8x M4 socket cap screws"
ref_plane "WorkPlane13" through (0, 0, 12) normal (0, 0, 1) x (1, 0, 0) in component "12 Cover perimeter bolts | 8x M4 socket cap screws"
sketch "BHead_5_112 sketch" plane through (0, 0, 12) normal (0, 0, 1) x (1, 0, 0) in component "12 Cover perimeter bolts | 8x M4 socket cap screws"
  circle A0 centre (5, 112) radius 3.5
extrude "BHead_5_112" add sketch "BHead_5_112 sketch" along normal blind 4 separate body makes body 26 in component "12 Cover perimeter bolts | 8x M4 socket cap screws"
ref_plane "WorkPlane14" through (0, 0, 12) normal (0, 0, 1) x (1, 0, 0) in component "12 Cover perimeter bolts | 8x M4 socket cap screws"
sketch "BShank_5_112 sketch" plane through (0, 0, 12) normal (0, 0, 1) x (1, 0, 0) in component "12 Cover perimeter bolts | 8x M4 socket cap screws"
  circle A0 centre (5, 112) radius 1.9
extrude "BShank_5_112" add sketch "BShank_5_112 sketch" against normal blind 18.5 bodies 26 in component "12 Cover perimeter bolts | 8x M4 socket cap screws"
ref_plane "WorkPlane15" through (0, 0, 12) normal (0, 0, 1) x (1, 0, 0) in component "12 Cover perimeter bolts | 8x M4 socket cap screws"
sketch "BHead_75_112 sketch" plane through (0, 0, 12) normal (0, 0, 1) x (1, 0, 0) in component "12 Cover perimeter bolts | 8x M4 socket cap screws"
  circle A0 centre (75, 112) radius 3.5
extrude "BHead_75_112" add sketch "BHead_75_112 sketch" along normal blind 4 separate body makes body 27 in component "12 Cover perimeter bolts | 8x M4 socket cap screws"
ref_plane "WorkPlane16" through (0, 0, 12) normal (0, 0, 1) x (1, 0, 0) in component "12 Cover perimeter bolts | 8x M4 socket cap screws"
sketch "BShank_75_112 sketch" plane through (0, 0, 12) normal (0, 0, 1) x (1, 0, 0) in component "12 Cover perimeter bolts | 8x M4 socket cap screws"
  circle A0 centre (75, 112) radius 1.9
extrude "BShank_75_112" add sketch "BShank_75_112 sketch" against normal blind 18.5 bodies 27 in component "12 Cover perimeter bolts | 8x M4 socket cap screws"
ref_plane "WorkPlane1" through (0, 0, -6.5) normal (0, 0, 1) x (1, 0, 0) in component "13 Cover nuts | 8x M4 hex nuts"
sketch "Nut_5_8 sketch" plane through (0, 0, -6.5) normal (0, 0, 1) x (1, 0, 0) in component "13 Cover nuts | 8x M4 hex nuts"
  circle A0 centre (5, 8) radius 3.8
extrude "Nut_5_8" add sketch "Nut_5_8 sketch" against normal blind 3 separate body makes body 28 in component "13 Cover nuts | 8x M4 hex nuts"
ref_plane "WorkPlane2" through (0, 0, -6.5) normal (0, 0, 1) x (1, 0, 0) in component "13 Cover nuts | 8x M4 hex nuts"
sketch "NutBore_5_8 sketch" plane through (0, 0, -6.5) normal (0, 0, 1) x (1, 0, 0) in component "13 Cover nuts | 8x M4 hex nuts"
  circle A0 centre (5, 8) radius 2
extrude "NutBore_5_8" cut sketch "NutBore_5_8 sketch" against normal blind 3 bodies 28 in component "13 Cover nuts | 8x M4 hex nuts"
ref_plane "WorkPlane3" through (0, 0, -6.5) normal (0, 0, 1) x (1, 0, 0) in component "13 Cover nuts | 8x M4 hex nuts"
sketch "Nut_75_8 sketch" plane through (0, 0, -6.5) normal (0, 0, 1) x (1, 0, 0) in component "13 Cover nuts | 8x M4 hex nuts"
  circle A0 centre (75, 8) radius 3.8
extrude "Nut_75_8" add sketch "Nut_75_8 sketch" against normal blind 3 separate body makes body 29 in component "13 Cover nuts | 8x M4 hex nuts"
ref_plane "WorkPlane4" through (0, 0, -6.5) normal (0, 0, 1) x (1, 0, 0) in component "13 Cover nuts | 8x M4 hex nuts"
sketch "NutBore_75_8 sketch" plane through (0, 0, -6.5) normal (0, 0, 1) x (1, 0, 0) in component "13 Cover nuts | 8x M4 hex nuts"
  circle A0 centre (75, 8) radius 2
extrude "NutBore_75_8" cut sketch "NutBore_75_8 sketch" against normal blind 3 bodies 29 in component "13 Cover nuts | 8x M4 hex nuts"
ref_plane "WorkPlane5" through (0, 0, -6.5) normal (0, 0, 1) x (1, 0, 0) in component "13 Cover nuts | 8x M4 hex nuts"
sketch "Nut_5_40 sketch" plane through (0, 0, -6.5) normal (0, 0, 1) x (1, 0, 0) in component "13 Cover nuts | 8x M4 hex nuts"
  circle A0 centre (5, 40) radius 3.8
extrude "Nut_5_40" add sketch "Nut_5_40 sketch" against normal blind 3 separate body makes body 30 in component "13 Cover nuts | 8x M4 hex nuts"
ref_plane "WorkPlane6" through (0, 0, -6.5) normal (0, 0, 1) x (1, 0, 0) in component "13 Cover nuts | 8x M4 hex nuts"
sketch "NutBore_5_40 sketch" plane through (0, 0, -6.5) normal (0, 0, 1) x (1, 0, 0) in component "13 Cover nuts | 8x M4 hex nuts"
  circle A0 centre (5, 40) radius 2
extrude "NutBore_5_40" cut sketch "NutBore_5_40 sketch" against normal blind 3 bodies 30 in component "13 Cover nuts | 8x M4 hex nuts"
ref_plane "WorkPlane7" through (0, 0, -6.5) normal (0, 0, 1) x (1, 0, 0) in component "13 Cover nuts | 8x M4 hex nuts"
sketch "Nut_75_40 sketch" plane through (0, 0, -6.5) normal (0, 0, 1) x (1, 0, 0) in component "13 Cover nuts | 8x M4 hex nuts"
  circle A0 centre (75, 40) radius 3.8
extrude "Nut_75_40" add sketch "Nut_75_40 sketch" against normal blind 3 separate body makes body 31 in component "13 Cover nuts | 8x M4 hex nuts"
ref_plane "WorkPlane8" through (0, 0, -6.5) normal (0, 0, 1) x (1, 0, 0) in component "13 Cover nuts | 8x M4 hex nuts"
sketch "NutBore_75_40 sketch" plane through (0, 0, -6.5) normal (0, 0, 1) x (1, 0, 0) in component "13 Cover nuts | 8x M4 hex nuts"
  circle A0 centre (75, 40) radius 2
extrude "NutBore_75_40" cut sketch "NutBore_75_40 sketch" against normal blind 3 bodies 31 in component "13 Cover nuts | 8x M4 hex nuts"
ref_plane "WorkPlane9" through (0, 0, -6.5) normal (0, 0, 1) x (1, 0, 0) in component "13 Cover nuts | 8x M4 hex nuts"
sketch "Nut_5_80 sketch" plane through (0, 0, -6.5) normal (0, 0, 1) x (1, 0, 0) in component "13 Cover nuts | 8x M4 hex nuts"
  circle A0 centre (5, 80) radius 3.8
extrude "Nut_5_80" add sketch "Nut_5_80 sketch" against normal blind 3 separate body makes body 32 in component "13 Cover nuts | 8x M4 hex nuts"
ref_plane "WorkPlane10" through (0, 0, -6.5) normal (0, 0, 1) x (1, 0, 0) in component "13 Cover nuts | 8x M4 hex nuts"
sketch "NutBore_5_80 sketch" plane through (0, 0, -6.5) normal (0, 0, 1) x (1, 0, 0) in component "13 Cover nuts | 8x M4 hex nuts"
  circle A0 centre (5, 80) radius 2
extrude "NutBore_5_80" cut sketch "NutBore_5_80 sketch" against normal blind 3 bodies 32 in component "13 Cover nuts | 8x M4 hex nuts"
ref_plane "WorkPlane11" through (0, 0, -6.5) normal (0, 0, 1) x (1, 0, 0) in component "13 Cover nuts | 8x M4 hex nuts"
sketch "Nut_75_80 sketch" plane through (0, 0, -6.5) normal (0, 0, 1) x (1, 0, 0) in component "13 Cover nuts | 8x M4 hex nuts"
  circle A0 centre (75, 80) radius 3.8
extrude "Nut_75_80" add sketch "Nut_75_80 sketch" against normal blind 3 separate body makes body 33 in component "13 Cover nuts | 8x M4 hex nuts"
ref_plane "WorkPlane12" through (0, 0, -6.5) normal (0, 0, 1) x (1, 0, 0) in component "13 Cover nuts | 8x M4 hex nuts"
sketch "NutBore_75_80 sketch" plane through (0, 0, -6.5) normal (0, 0, 1) x (1, 0, 0) in component "13 Cover nuts | 8x M4 hex nuts"
  circle A0 centre (75, 80) radius 2
extrude "NutBore_75_80" cut sketch "NutBore_75_80 sketch" against normal blind 3 bodies 33 in component "13 Cover nuts | 8x M4 hex nuts"
ref_plane "WorkPlane13" through (0, 0, -6.5) normal (0, 0, 1) x (1, 0, 0) in component "13 Cover nuts | 8x M4 hex nuts"
sketch "Nut_5_112 sketch" plane through (0, 0, -6.5) normal (0, 0, 1) x (1, 0, 0) in component "13 Cover nuts | 8x M4 hex nuts"
  circle A0 centre (5, 112) radius 3.8
extrude "Nut_5_112" add sketch "Nut_5_112 sketch" against normal blind 3 separate body makes body 34 in component "13 Cover nuts | 8x M4 hex nuts"
ref_plane "WorkPlane14" through (0, 0, -6.5) normal (0, 0, 1) x (1, 0, 0) in component "13 Cover nuts | 8x M4 hex nuts"
sketch "NutBore_5_112 sketch" plane through (0, 0, -6.5) normal (0, 0, 1) x (1, 0, 0) in component "13 Cover nuts | 8x M4 hex nuts"
  circle A0 centre (5, 112) radius 2
extrude "NutBore_5_112" cut sketch "NutBore_5_112 sketch" against normal blind 3 bodies 34 in component "13 Cover nuts | 8x M4 hex nuts"
ref_plane "WorkPlane15" through (0, 0, -6.5) normal (0, 0, 1) x (1, 0, 0) in component "13 Cover nuts | 8x M4 hex nuts"
sketch "Nut_75_112 sketch" plane through (0, 0, -6.5) normal (0, 0, 1) x (1, 0, 0) in component "13 Cover nuts | 8x M4 hex nuts"
  circle A0 centre (75, 112) radius 3.8
extrude "Nut_75_112" add sketch "Nut_75_112 sketch" against normal blind 3 separate body makes body 35 in component "13 Cover nuts | 8x M4 hex nuts"
ref_plane "WorkPlane16" through (0, 0, -6.5) normal (0, 0, 1) x (1, 0, 0) in component "13 Cover nuts | 8x M4 hex nuts"
sketch "NutBore_75_112 sketch" plane through (0, 0, -6.5) normal (0, 0, 1) x (1, 0, 0) in component "13 Cover nuts | 8x M4 hex nuts"
  circle A0 centre (75, 112) radius 2
extrude "NutBore_75_112" cut sketch "NutBore_75_112 sketch" against normal blind 3 bodies 35 in component "13 Cover nuts | 8x M4 hex nuts"
ref_plane "WorkPlane1" through (0, 0, 6.5) normal (0, 0, 1) x (1, 0, 0) in component "14 K-Type Thermocouple Sensor Assembly"
sketch "Sensor probe in thermowell sketch" plane through (0, 0, 6.5) normal (0, 0, 1) x (1, 0, 0) in component "14 K-Type Thermocouple Sensor Assembly"
  circle A0 centre (80, 60) radius 1.5
extrude "Sensor probe in thermowell" add sketch "Sensor probe in thermowell sketch" along normal blind 2 separate body makes body 36 in component "14 K-Type Thermocouple Sensor Assembly"
ref_plane "WorkPlane2" through (0, 0, 6.5) normal (0, 0, 1) x (1, 0, 0) in component "14 K-Type Thermocouple Sensor Assembly"
sketch "Probe sheath sketch" plane through (0, 0, 6.5) normal (0, 0, 1) x (1, 0, 0) in component "14 K-Type Thermocouple Sensor Assembly"
  circle A0 centre (84, 60) radius 1.5
extrude "Probe sheath" add sketch "Probe sheath sketch" along normal blind 2 separate body makes body 37 in component "14 K-Type Thermocouple Sensor Assembly"
ref_plane "WorkPlane3" through (0, 0, 5.5) normal (0, 0, 1) x (1, 0, 0) in component "14 K-Type Thermocouple Sensor Assembly"
sketch "Brass compression gland sketch" plane through (0, 0, 5.5) normal (0, 0, 1) x (1, 0, 0) in component "14 K-Type Thermocouple Sensor Assembly"
  circle A0 centre (88, 60) radius 3.2
extrude "Brass compression gland" add sketch "Brass compression gland sketch" along normal blind 4 bodies 37 in component "14 K-Type Thermocouple Sensor Assembly"
ref_plane "WorkPlane4" through (0, 0, 3) normal (0, 0, 1) x (1, 0, 0) in component "14 K-Type Thermocouple Sensor Assembly"